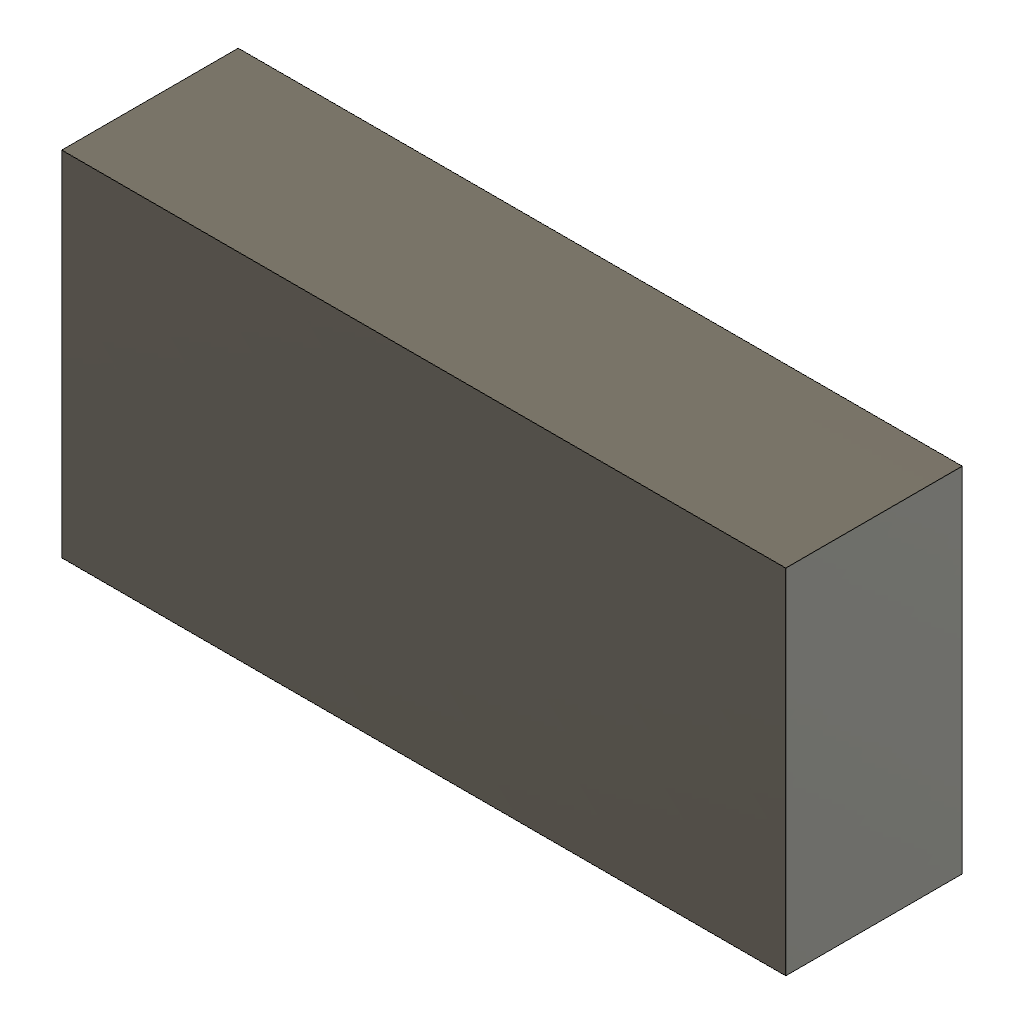
P03-fusion-edit-width_mm-41 (Autodesk Fusion 360 design; units mm, degrees)
part number: 2026-11-14-20-01-35-576
Autodesk Fusion 360 part; units mm, degrees
sketch "RectangleSketch" plane through (0, 0, 0) normal (0, 0, 1) x (1, 0, 0)
  line L0 (0, 0) -> (41, 0)
  line L1 (41, 0) -> (41, 20)
  line L2 (41, 20) -> (0, 20)
  line L3 (0, 20) -> (0, 0)
  dimension "width_mm" = 41
  dimension "height_mm" = 20
  constraint horizontal L0
  constraint vertical L1
  constraint horizontal L2
  constraint vertical L3
  constraint coincident L0.start L3.end
  measures "width_mm" horizontal distance of L0.start L0.end
  measures "height_mm" vertical distance of L0.start L2.end
extrude "BlindBoss" add sketch "RectangleSketch" along normal blind 10
equation "depth_mm = 10 mm"
